CBP-0000-RevD-CAD-checkpoint001 (Autodesk Fusion 360 design; units mm, degrees)
part number: 2026-09-21-21-13-08-575
part number: 2026-09-22-14-43-03-767
part number: 2026-09-22-14-43-32-423
Autodesk Fusion 360 part; units mm, degrees
sketch "SK-1100-01_BASE_OUTLINE_400x400" plane through (0, 0, 0) normal (0, 1, 0) x (1, 0, 0) in component "CBP-1100_BASE_PLATE"
  line L0 (200, 200) -> (-200, 200)
  line L1 (-200, 200) -> (-200, -200)
  line L2 (-200, -200) -> (200, -200)
  line L3 (200, -200) -> (200, 200)
  line L4 (200, 200) -> (-200, -200) construction
  line L5 (-200, 200) -> (200, -200) construction
  dimension "d4" = 400
  dimension "d5" = 400
  constraint horizontal L0
  constraint perpendicular L0 L1
  constraint parallel L0 L2
  constraint parallel L1 L3
  constraint coincident L4 origin
  constraint coincident L5 origin
  measures "d4" distance of L0.start L0.end
  measures "d5" distance of L0 L2
extrude "EX-1100-01_BASE_STOCK" add sketch "SK-1100-01_BASE_OUTLINE_400x400" along normal blind 12 in component "CBP-1100_BASE_PLATE"
sketch "SK-1100-02_CLEARANCE_APERTURE" plane through (0, 0, 0) normal (0, 1, 0) x (1, 0, 0) in component "CBP-1100_BASE_PLATE"
  line L0 (74, 49) -> (-74, 49)
  line L1 (-74, 49) -> (-74, -49)
  line L2 (-74, -49) -> (74, -49)
  line L3 (74, -49) -> (74, 49)
  dimension "d56" = 148
  dimension "d57" = 98
  dimension "d58" = 74
  dimension "d59" = 49
  constraint horizontal L0
  constraint vertical L1
  constraint horizontal L2
  constraint vertical L3
  measures "d56" horizontal distance of L0.start L0.end
  measures "d57" vertical distance of L0.end L1.end
  measures "d58" horizontal distance of origin L0.start
  measures "d59" vertical distance of origin L0.start
extrude "CUT-1100-01_BED_SWEEP_APERTURE" cut sketch "SK-1100-02_CLEARANCE_APERTURE" along normal blind 12 in component "CBP-1100_BASE_PLATE"
sketch "SK-1100-03_FOUR_BASE_MOUNTS" plane through (0, 0, 0) normal (0, 1, 0) x (1, 0, 0) in component "CBP-1100_BASE_PLATE"
  circle A0 centre (-180, -180) radius 4.5
  circle A1 centre (-180, 180) radius 4.5
  circle A2 centre (180, -180) radius 4.5
  circle A3 centre (180, 180) radius 4.5
  dimension "d62" = 180
  dimension "d63" = 180
  dimension "d64" = 9
  dimension "d65" = 180
  dimension "d66" = 180
  constraint vertical A0.centre A1.centre
  constraint equal A0 A1
  constraint horizontal A0.centre A2.centre
  constraint equal A0 A2
  constraint vertical A2.centre A3.centre
  constraint horizontal A1.centre A3.centre
  constraint equal A0 A3
  measures "d62" horizontal distance of origin A0.centre
  measures "d63" vertical distance of origin A0.centre
  measures "d64" diameter of A0
  measures "d65" vertical distance of origin A1.centre
  measures "d66" horizontal distance of origin A2.centre
extrude "CUT-1100-02_FOUR_M8_MOUNTS" cut sketch "SK-1100-03_FOUR_BASE_MOUNTS" along normal blind 12 in component "CBP-1100_BASE_PLATE"
component "10_FRAME" placed x (1, 0, 0) y (0, 1, 0) z (0, 0, 1) at (0, 0, 0)
component "CBP-1100_BASE_PLATE" placed x (1, 0, 0) y (0, 1, 0) z (0, 0, 1) at (0, 0, 0) in component "10_FRAME"
equation "base_x = 400 mm"
equation "base_y = 400 mm"
equation "base_t = 12 mm"
equation "d4 = base_x"
equation "d5 = base_y"
equation "d6 = base_t"
equation "base_bolt_inset = 20 mm" comment "Edge to mounting hole center"
equation "base_mount_d = 9 mm" comment "M8 clearance through holes"
equation "base_corner_r = 8 mm" comment "Outside vertical corner radius"
equation "travel_x = 64 mm" comment "Nominal useful X travel"
equation "travel_y = 40 mm" comment "Nominal useful Y travel"
equation "travel_z = 60 mm" comment "Useful nozzle Z range"
equation "bed_x = 76 mm" comment "Build surface X"
equation "bed_y = 50 mm" comment "Build surface Y"
equation "bed_t = 3 mm" comment "Development bed carrier thickness"
equation "bed_surface_t = 0.25 mm" comment "Build surface film allowance"
equation "stage_x = 220 mm" comment "Planar carrier outer X envelope; provisional"
equation "stage_y = 150 mm" comment "Planar carrier outer Y envelope; provisional"
equation "stage_t = 3 mm" comment "Carrier material thickness; provisional"
equation "guide_x = 320 mm" comment "Planar guide envelope X"
equation "guide_y = 260 mm" comment "Planar guide envelope Y"
equation "guide_t = 6 mm" comment "Guide plate stock allowance"
equation "guide_gap = 0.08 mm" comment "Prototype capture clearance; must verify fabrication"
equation "aperture_x = bed_x + travel_x + 8 mm" comment "Minimum bed and boat swept aperture X"
equation "aperture_y = bed_y + travel_y + 8 mm" comment "Minimum bed and boat swept aperture Y"
equation "tower_span = 320 mm" comment "Z tower outside support span"
equation "tower_y = 150 mm" comment "Tower axis Y from machine origin"
equation "tower_h = 280 mm" comment "Tower support height above base"
equation "tower_section = 40 mm" comment "Structural column nominal section"
equation "motor_flange = 56.4 mm" comment "Nanotec SCB5618L4204-B reference envelope only"
equation "motor_body_l = 76.5 mm" comment "Motor reference body length"
equation "motor_shaft_d = 8 mm" comment "Motor reference shaft diameter"
equation "drum_r = 25 mm" comment "Drive drum pitch radius; adjustable development parameter"
equation "belt_w = 9 mm" comment "Owned belt width; pitch and interfaces unconfirmed"
equation "anchor_x = 150 mm" comment "Drive anchor reference X offset"
equation "anchor_y = 150 mm" comment "Drive anchor reference Y offset"
equation "hose_od = 22 mm" comment "Provisional hose outside diameter; owned hose to be identified"
equation "hotend_z_envelope = 180 mm" comment "Stationary XY extrusion envelope allowance"
equation "toolhead_xy_envelope = 140 mm" comment "Multi-input extrusion service envelope"
equation "nozzle_d = 0.5 mm" comment "Maximum nozzle under retained race rules"
equation "fastener_m3_clear = 3.4 mm" comment "Ordinary M3 clearance"
equation "fastener_m5_clear = 5.5 mm" comment "Ordinary M5 clearance"
equation "fastener_m6_clear = 6.6 mm" comment "Ordinary M6 clearance"
equation "d56 = aperture_x"
equation "d57 = aperture_y"
equation "d58 = aperture_x / 2"
equation "d59 = aperture_y / 2"
equation "d60 = base_t"
equation "d62 = base_x / 2 - base_bolt_inset"
equation "d63 = base_y / 2 - base_bolt_inset"
equation "d64 = base_mount_d"
equation "d65 = base_y / 2 - base_bolt_inset"
equation "d66 = base_x / 2 - base_bolt_inset"
equation "d67 = base_t"
named bodies: "CBP-1100_BASE_STOCK"
